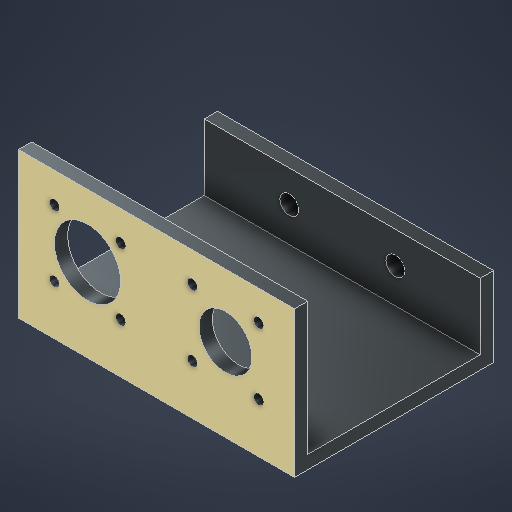
# Autodesk Inventor part: s1101mfa1026
Saved by Autodesk Inventor 2027.1 (Build 311270010, 270A)
## iProperties
Created: 2026-10-31
Part Number: s1101mfa1026
Material: Generic
Document SubType Name: Modeling
Designer: User
Density: 1 g/cm^3
Appearance: Iron Gray
Author: User
Autodesk Inventor part; units mm, degrees
ref_plane "YZ Plane" through (0, 0, 0) normal (1, 0, 0) x (0, 1, 0)
ref_plane "XZ Plane" through (0, 0, 0) normal (0, 1, 0) x (-1, 0, 0)
sketch "Sketch1" plane through (0, 0, 0) normal (1, 0, 0) x (0, 1, 0)
  line L0 (0, 0) -> (19.05, 0)
  line L1 (19.05, 0) -> (19.05, 3.175)
  line L2 (19.05, 3.175) -> (3.175, 3.175)
  line L3 (3.175, 3.175) -> (3.175, 44.45)
  line L4 (3.175, 44.45) -> (34.925, 44.45)
  line L5 (34.925, 44.45) -> (34.925, 47.625)
  line L6 (34.925, 47.625) -> (0, 47.625)
  line L7 (0, 47.625) -> (0, 0)
  constraints: 16 end point
extrude "Extrusion1" add sketch "Sketch1" along normal mid plane 66.04
sketch "Sketch2" plane through (0, 0, 0) normal (0, 0, 1) x (1, 0, 0)
  circle A0 centre (-12.7, 11.43) radius 2.2352
  circle A1 centre (12.7, 11.43) radius 2.2352
  constraints: 2 centre point
extrude "Extrusion2" cut sketch "Sketch2" along normal mid plane 7.62
ref_plane "Work Plane1" through (0, 0, 47.625) normal (0, 0, 1) x (1, 0, 0)
sketch "Sketch3" plane through (0, 0, 47.625) normal (0, 0, 1) x (1, 0, 0)
  circle A0 centre (-16.51, 19.812) radius 7.9375
  circle A1 centre (-24.4348, 11.8872) radius 1.2192
  circle A2 centre (-24.4348, 27.7368) radius 1.2192
  circle A3 centre (-8.5852, 11.8872) radius 1.2192
  circle A4 centre (-8.5852, 27.7368) radius 1.2192
  circle A5 centre (16.51, 19.812) radius 6.35
  circle A6 centre (8.5852, 11.8872) radius 1.2192
  circle A7 centre (8.5852, 27.7368) radius 1.2192
  circle A8 centre (24.4348, 11.8872) radius 1.2192
  circle A9 centre (24.4348, 27.7368) radius 1.2192
  constraints: 10 centre point
extrude "Extrusion3" cut sketch "Sketch3" along normal mid plane 7.62
body "Solid1"
